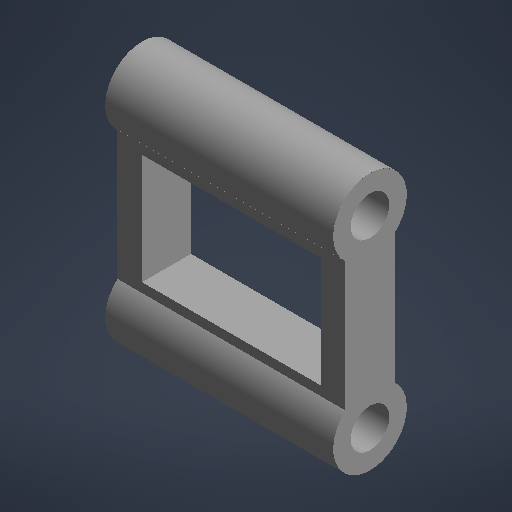
# Autodesk Inventor part: R2_muslo_link_izq
Saved by Autodesk Inventor 2027 (Build 310192060, 192F)
## iProperties
Part Number: R2_muslo_link_izq
Material: Genérico
Document SubType Name: Modelado
Designer: rodri
Appearance: Por defecto
Author: rodri
Autodesk Inventor part; units mm, degrees
ref_plane "Plano de trabajo1" through (0, 0, 3.5) normal (0, 0, 1) x (1, 0, 0)
sketch "Boceto1" plane through (0, 0, 3.5) normal (0, 0, 1) x (1, 0, 0)
  line L0 (12.8, -78) -> (50, -78)
  line L1 (50, -78) -> (50, -48)
  line L2 (50, -48) -> (12.8, -48)
  line L3 (12.8, -48) -> (12.8, -78)
  constraints: 8 end point, 2 parallel, 1 horizontal, 1 perpendicular
extrude "Extrusión1" add sketch "Boceto1" along normal blind 8
ref_plane "Plano de trabajo2" through (12.8, 0, 0) normal (1, 0, 0) x (0, 1, 0)
sketch "Boceto2" plane through (12.8, 0, 0) normal (1, 0, 0) x (0, 1, 0)
  circle A0 centre (-48, 7.5) radius 6
  constraints: 1 centre point
extrude "Extrusión2" add sketch "Boceto2" along normal blind 37.2
ref_plane "Plano de trabajo3" through (12.8, 0, 0) normal (1, 0, 0) x (0, 1, 0)
sketch "Boceto3" plane through (12.8, 0, 0) normal (1, 0, 0) x (0, 1, 0)
  circle A0 centre (-78, 7.5) radius 6
  constraints: 1 centre point
extrude "Extrusión3" add sketch "Boceto3" along normal blind 37.2
ref_plane "Plano de trabajo4" through (0, 0, 3.4) normal (0, 0, 1) x (1, 0, 0)
sketch "Boceto4" plane through (0, 0, 3.4) normal (0, 0, 1) x (1, 0, 0)
  line L0 (16.8, -72) -> (46, -72)
  line L1 (46, -72) -> (46, -54)
  line L2 (46, -54) -> (16.8, -54)
  line L3 (16.8, -54) -> (16.8, -72)
  constraints: 8 end point, 2 parallel, 1 horizontal, 1 perpendicular
extrude "Extrusión4" cut sketch "Boceto4" along normal blind 8.2
ref_plane "Plano de trabajo5" through (12.7, 0, 0) normal (1, 0, 0) x (0, 1, 0)
sketch "Boceto5" plane through (12.7, 0, 0) normal (1, 0, 0) x (0, 1, 0)
  circle A0 centre (-78, 7.5) radius 3.15
  constraints: 1 centre point
extrude "Extrusión5" cut sketch "Boceto5" along normal blind 37.4
ref_plane "Plano de trabajo6" through (12.7, 0, 0) normal (1, 0, 0) x (0, 1, 0)
sketch "Boceto6" plane through (12.7, 0, 0) normal (1, 0, 0) x (0, 1, 0)
  circle A0 centre (-48, 7.5) radius 3.15
  constraints: 1 centre point
extrude "Extrusión6" cut sketch "Boceto6" along normal blind 37.4
